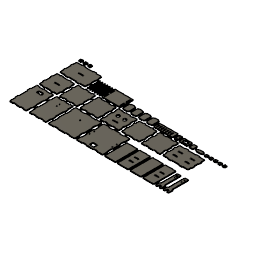
ROBERTO_PECAS_ESPALHADAS (Autodesk Fusion 360 design; units mm, degrees)
part number: 2026-10-26-13-50-44-096
part number: 2026-10-26-13-50-44-308
part number: 2026-10-26-13-50-44-466
part number: 2026-10-26-13-50-44-592
part number: 2026-10-26-13-50-44-704
part number: 2026-10-26-13-50-44-855
part number: 2026-10-26-13-50-44-911
part number: 2026-10-26-13-50-44-996
part number: 2026-10-26-13-50-45-058
part number: 2026-10-26-13-50-45-187
part number: 2026-10-26-13-50-45-294
part number: 2026-10-26-13-50-45-413
part number: 2026-10-26-13-50-45-575
part number: 2026-10-26-13-50-45-725
part number: 2026-10-26-13-50-45-862
part number: 2026-10-26-13-50-46-044
part number: 2026-10-26-13-50-46-201
part number: 2026-10-26-13-50-46-377
part number: 2026-10-26-13-50-46-593
part number: 2026-10-26-13-50-46-819
part number: 2026-10-26-13-50-46-915
part number: 2026-10-26-13-50-47-022
part number: 2026-10-26-13-50-47-157
part number: 2026-10-26-13-50-47-275
part number: 2026-10-26-13-50-47-377
part number: 2026-10-26-13-50-47-495
part number: 2026-10-26-13-50-47-649
part number: 2026-10-26-13-50-47-793
part number: 2026-10-26-13-50-47-947
part number: 2026-10-26-13-50-48-095
part number: 2026-10-26-13-50-48-228
part number: 2026-10-26-13-50-48-464
part number: 2026-10-26-13-50-48-602
part number: 2026-10-26-13-50-48-754
part number: 2026-10-26-13-50-48-889
part number: 2026-10-26-13-50-49-059
part number: 2026-10-26-13-50-49-210
part number: 2026-10-26-13-50-49-351
part number: 2026-10-26-13-50-49-502
part number: 2026-10-26-13-50-49-657
part number: 2026-10-26-13-50-49-817
part number: 2026-10-26-13-50-49-993
part number: 2026-10-26-13-50-50-198
Autodesk Fusion 360 part; units mm, degrees
sketch "Esboço1" plane through (0, 0, 0) normal (0, 0, 1) x (1, 0, 0) in component "C_DIR"
  line L0 (36.1, 0) -> (58.9, 0)
  line L1 (58.9, 0) -> (58.9, 3.1)
  line L2 (58.9, 3.1) -> (74.1, 3.1)
  line L3 (74.1, 3.1) -> (74.1, 0)
  line L4 (74.1, 0) -> (92, 0)
  line L5 (92, 0) -> (92, 29.25)
  line L6 (92, 29.25) -> (95, 29.25)
  line L7 (95, 29.25) -> (95, 51.05)
  line L8 (95, 51.05) -> (92, 51.05)
  line L9 (92, 51.05) -> (92, 94.95)
  line L10 (92, 94.95) -> (95, 94.95)
  line L11 (95, 94.95) -> (95, 116.75)
  line L12 (95, 116.75) -> (92, 116.75)
  line L13 (92, 116.75) -> (92, 146)
  line L14 (92, 146) -> (74.1, 146)
  line L15 (74.1, 146) -> (74.1, 142.9)
  line L16 (74.1, 142.9) -> (58.9, 142.9)
  line L17 (58.9, 142.9) -> (58.9, 146)
  line L18 (58.9, 146) -> (36.1, 146)
  line L19 (36.1, 146) -> (36.1, 142.9)
  line L20 (36.1, 142.9) -> (20.9, 142.9)
  line L21 (20.9, 142.9) -> (20.9, 146)
  line L22 (20.9, 146) -> (3, 146)
  line L23 (3, 146) -> (3, 116.75)
  line L24 (3, 116.75) -> (0, 116.75)
  line L25 (0, 116.75) -> (0, 94.95)
  line L26 (0, 94.95) -> (3, 94.95)
  line L27 (3, 94.95) -> (3, 51.05)
  line L28 (3, 51.05) -> (0, 51.05)
  line L29 (0, 51.05) -> (0, 29.25)
  line L30 (0, 29.25) -> (3, 29.25)
  line L31 (3, 29.25) -> (3, 0)
  line L32 (3, 0) -> (20.9, 0)
  line L33 (20.9, 0) -> (20.9, 3.1)
  line L34 (20.9, 3.1) -> (36.1, 3.1)
  line L35 (36.1, 3.1) -> (36.1, 0)
  line L36 (35.75, 111.6) -> (35.75, 124.4)
  line L37 (35.75, 124.4) -> (59.25, 124.4)
  line L38 (59.25, 124.4) -> (59.25, 111.6)
  line L39 (59.25, 111.6) -> (35.75, 111.6)
  circle A0 centre (33.5, 118) radius 1.1
  circle A1 centre (61.5, 118) radius 1.1
extrude "C_DIR" add sketch "Esboço1" along normal blind 3 makes body 1 in component "C_DIR"
sketch "Esboço1 (2)" plane through (0, 0, 0) normal (0, 0, 1) x (1, 0, 0) in component "C_ESQ"
  line L0 (92, 29.25) -> (95, 29.25)
  line L1 (95, 29.25) -> (95, 51.05)
  line L2 (95, 51.05) -> (92, 51.05)
  line L3 (92, 51.05) -> (92, 94.95)
  line L4 (92, 94.95) -> (95, 94.95)
  line L5 (95, 94.95) -> (95, 116.75)
  line L6 (95, 116.75) -> (92, 116.75)
  line L7 (92, 116.75) -> (92, 146)
  line L8 (92, 146) -> (74.1, 146)
  line L9 (74.1, 146) -> (74.1, 142.9)
  line L10 (74.1, 142.9) -> (58.9, 142.9)
  line L11 (58.9, 142.9) -> (58.9, 146)
  line L12 (58.9, 146) -> (36.1, 146)
  line L13 (36.1, 146) -> (36.1, 142.9)
  line L14 (36.1, 142.9) -> (20.9, 142.9)
  line L15 (20.9, 142.9) -> (20.9, 146)
  line L16 (20.9, 146) -> (3, 146)
  line L17 (3, 146) -> (3, 116.75)
  line L18 (3, 116.75) -> (0, 116.75)
  line L19 (0, 116.75) -> (0, 94.95)
  line L20 (0, 94.95) -> (3, 94.95)
  line L21 (3, 94.95) -> (3, 51.05)
  line L22 (3, 51.05) -> (0, 51.05)
  line L23 (0, 51.05) -> (0, 29.25)
  line L24 (0, 29.25) -> (3, 29.25)
  line L25 (3, 29.25) -> (3, 0)
  line L26 (3, 0) -> (20.9, 0)
  line L27 (20.9, 0) -> (20.9, 3.1)
  line L28 (20.9, 3.1) -> (36.1, 3.1)
  line L29 (36.1, 3.1) -> (36.1, 0)
  line L30 (36.1, 0) -> (58.9, 0)
  line L31 (58.9, 0) -> (58.9, 3.1)
  line L32 (58.9, 3.1) -> (74.1, 3.1)
  line L33 (74.1, 3.1) -> (74.1, 0)
  line L34 (74.1, 0) -> (92, 0)
  line L35 (92, 0) -> (92, 29.25)
  circle A0 centre (47.5, 118) radius 1.7
  circle A1 centre (47.5, 103) radius 1.7
extrude "C_ESQ" add sketch "Esboço1 (2)" along normal blind 3 separate body makes body 2 in component "C_ESQ"
sketch "Esboço1 (3)" plane through (0, 0, 0) normal (0, 0, 1) x (1, 0, 0) in component "C_FRENTE"
  line L0 (136.9, 94.9) -> (136.9, 116.8)
  line L1 (136.9, 116.8) -> (140, 116.8)
  line L2 (140, 116.8) -> (140, 146)
  line L3 (140, 146) -> (109.2, 146)
  line L4 (109.2, 146) -> (109.2, 142.9)
  line L5 (109.2, 142.9) -> (89.6, 142.9)
  line L6 (89.6, 142.9) -> (89.6, 146)
  line L7 (89.6, 146) -> (50.4, 146)
  line L8 (50.4, 146) -> (50.4, 142.9)
  line L9 (50.4, 142.9) -> (30.8, 142.9)
  line L10 (30.8, 142.9) -> (30.8, 146)
  line L11 (30.8, 146) -> (0, 146)
  line L12 (0, 146) -> (0, 116.8)
  line L13 (0, 116.8) -> (3.1, 116.8)
  line L14 (3.1, 116.8) -> (3.1, 94.9)
  line L15 (3.1, 94.9) -> (0, 94.9)
  line L16 (0, 94.9) -> (0, 51.1)
  line L17 (0, 51.1) -> (3.1, 51.1)
  line L18 (3.1, 51.1) -> (3.1, 29.2)
  line L19 (3.1, 29.2) -> (0, 29.2)
  line L20 (0, 29.2) -> (0, 0)
  line L21 (0, 0) -> (30.8, 0)
  line L22 (30.8, 0) -> (30.8, 3.1)
  line L23 (30.8, 3.1) -> (50.4, 3.1)
  line L24 (50.4, 3.1) -> (50.4, 0)
  line L25 (50.4, 0) -> (89.6, 0)
  line L26 (89.6, 0) -> (89.6, 3.1)
  line L27 (89.6, 3.1) -> (109.2, 3.1)
  line L28 (109.2, 3.1) -> (109.2, 0)
  line L29 (109.2, 0) -> (140, 0)
  line L30 (140, 0) -> (140, 29.2)
  line L31 (140, 29.2) -> (136.9, 29.2)
  line L32 (136.9, 29.2) -> (136.9, 51.1)
  line L33 (136.9, 51.1) -> (140, 51.1)
  line L34 (140, 51.1) -> (140, 94.9)
  line L35 (140, 94.9) -> (136.9, 94.9)
  circle A0 centre (70, 99.28) radius 2.6
extrude "C_FRENTE" add sketch "Esboço1 (3)" along normal blind 3 separate body makes body 3 in component "C_FRENTE"
sketch "Esboço1 (4)" plane through (0, 0, 0) normal (0, 0, 1) x (1, 0, 0) in component "C_TRAS"
  line L0 (89.6, 0) -> (89.6, 3.1)
  line L1 (89.6, 3.1) -> (109.2, 3.1)
  line L2 (109.2, 3.1) -> (109.2, 0)
  line L3 (109.2, 0) -> (140, 0)
  line L4 (140, 0) -> (140, 29.2)
  line L5 (140, 29.2) -> (136.9, 29.2)
  line L6 (136.9, 29.2) -> (136.9, 51.1)
  line L7 (136.9, 51.1) -> (140, 51.1)
  line L8 (140, 51.1) -> (140, 94.9)
  line L9 (140, 94.9) -> (136.9, 94.9)
  line L10 (136.9, 94.9) -> (136.9, 116.8)
  line L11 (136.9, 116.8) -> (140, 116.8)
  line L12 (140, 116.8) -> (140, 146)
  line L13 (140, 146) -> (109.2, 146)
  line L14 (109.2, 146) -> (109.2, 142.9)
  line L15 (109.2, 142.9) -> (89.6, 142.9)
  line L16 (89.6, 142.9) -> (89.6, 146)
  line L17 (89.6, 146) -> (50.4, 146)
  line L18 (50.4, 146) -> (50.4, 142.9)
  line L19 (50.4, 142.9) -> (30.8, 142.9)
  line L20 (30.8, 142.9) -> (30.8, 146)
  line L21 (30.8, 146) -> (0, 146)
  line L22 (0, 146) -> (0, 116.8)
  line L23 (0, 116.8) -> (3.1, 116.8)
  line L24 (3.1, 116.8) -> (3.1, 94.9)
  line L25 (3.1, 94.9) -> (0, 94.9)
  line L26 (0, 94.9) -> (0, 51.1)
  line L27 (0, 51.1) -> (3.1, 51.1)
  line L28 (3.1, 51.1) -> (3.1, 29.2)
  line L29 (3.1, 29.2) -> (0, 29.2)
  line L30 (0, 29.2) -> (0, 0)
  line L31 (0, 0) -> (30.8, 0)
  line L32 (30.8, 0) -> (30.8, 3.1)
  line L33 (30.8, 3.1) -> (50.4, 3.1)
  line L34 (50.4, 3.1) -> (50.4, 0)
  line L35 (50.4, 0) -> (89.6, 0)
  line L36 (58, 30) -> (82, 30)
  line L37 (82, 30) -> (82, 12)
  line L38 (82, 12) -> (58, 12)
  line L39 (58, 12) -> (58, 30)
  circle A0 centre (10, 61.32) radius 1.7
  circle A1 centre (10, 84.68) radius 1.7
  circle A2 centre (130, 61.32) radius 1.7
  circle A3 centre (130, 84.68) radius 1.7
extrude "C_TRAS" add sketch "Esboço1 (4)" along normal blind 3 separate body makes body 4 in component "C_TRAS"
sketch "Esboço1 (5)" plane through (0, 0, 0) normal (0, 0, 1) x (1, 0, 0) in component "P_D1"
  line L0 (0, 0) -> (58, 0)
  line L1 (58, 0) -> (58, 120)
  line L2 (58, 120) -> (0, 120)
  line L3 (0, 120) -> (0, 0)
extrude "P_D1" add sketch "Esboço1 (5)" along normal blind 3 separate body makes body 5 in component "P_D1"
sketch "Esboço1 (6)" plane through (0, 0, 0) normal (0, 0, 1) x (1, 0, 0) in component "P_D2"
  line L0 (18.95, 44.2) -> (18.95, 47.3)
  line L1 (18.95, 47.3) -> (39.05, 47.3)
  line L2 (39.05, 47.3) -> (39.05, 44.2)
  line L3 (39.05, 44.2) -> (18.95, 44.2)
  line L4 (0, 0) -> (58, 0)
  line L5 (58, 0) -> (58, 120)
  line L6 (58, 120) -> (0, 120)
  line L7 (0, 120) -> (0, 0)
  line L8 (39.05, 72.7) -> (18.95, 72.7)
  line L9 (18.95, 72.7) -> (18.95, 75.8)
  line L10 (18.95, 75.8) -> (39.05, 75.8)
  line L11 (39.05, 75.8) -> (39.05, 72.7)
extrude "P_D2" add sketch "Esboço1 (6)" along normal blind 3 separate body makes body 6 in component "P_D2"
sketch "Esboço1 (7)" plane through (0, 0, 0) normal (0, 0, 1) x (1, 0, 0) in component "P_E1"
  line L0 (0, 0) -> (58, 0)
  line L1 (58, 0) -> (58, 120)
  line L2 (58, 120) -> (0, 120)
  line L3 (0, 120) -> (0, 0)
extrude "P_E1" add sketch "Esboço1 (7)" along normal blind 3 separate body makes body 7 in component "P_E1"
sketch "Esboço1 (8)" plane through (0, 0, 0) normal (0, 0, 1) x (1, 0, 0) in component "P_E2"
  line L0 (18.95, 44.2) -> (18.95, 47.3)
  line L1 (18.95, 47.3) -> (39.05, 47.3)
  line L2 (39.05, 47.3) -> (39.05, 44.2)
  line L3 (39.05, 44.2) -> (18.95, 44.2)
  line L4 (0, 0) -> (58, 0)
  line L5 (58, 0) -> (58, 120)
  line L6 (58, 120) -> (0, 120)
  line L7 (0, 120) -> (0, 0)
  line L8 (39.05, 72.7) -> (18.95, 72.7)
  line L9 (18.95, 72.7) -> (18.95, 75.8)
  line L10 (18.95, 75.8) -> (39.05, 75.8)
  line L11 (39.05, 75.8) -> (39.05, 72.7)
extrude "P_E2" add sketch "Esboço1 (8)" along normal blind 3 separate body makes body 8 in component "P_E2"
sketch "Esboço1 (9)" plane through (0, 0, 0) normal (0, 0, 1) x (1, 0, 0) in component "A_D_MOVEL"
  line L0 (-10, 12) -> (10, 12)
  line L1 (10, 12) -> (10, -75)
  line L2 (10, -75) -> (15, -75)
  line L3 (15, -75) -> (15, -100)
  line L4 (15, -100) -> (5, -100)
  line L5 (5, -100) -> (5, -88)
  line L6 (5, -88) -> (-5, -88)
  line L7 (-5, -88) -> (-5, -100)
  line L8 (-5, -100) -> (-15, -100)
  line L9 (-15, -100) -> (-15, -75)
  line L10 (-15, -75) -> (-10, -75)
  line L11 (-10, -75) -> (-10, 12)
  circle A0 centre (0, 0) radius 3.5
  circle A1 centre (0, -7) radius 1
  circle A2 centre (0, -14) radius 1
extrude "A_D_MOVEL" add sketch "Esboço1 (9)" along normal blind 3 separate body makes body 9 in component "A_D_MOVEL"
sketch "Esboço1 (10)" plane through (0, 0, 0) normal (0, 0, 1) x (1, 0, 0) in component "A_E_FIXO"
  line L0 (-10, 12) -> (10, 12)
  line L1 (10, 12) -> (10, -75)
  line L2 (10, -75) -> (15, -75)
  line L3 (15, -75) -> (15, -100)
  line L4 (15, -100) -> (5, -100)
  line L5 (5, -100) -> (5, -88)
  line L6 (5, -88) -> (-5, -88)
  line L7 (-5, -88) -> (-5, -100)
  line L8 (-5, -100) -> (-15, -100)
  line L9 (-15, -100) -> (-15, -75)
  line L10 (-15, -75) -> (-10, -75)
  line L11 (-10, -75) -> (-10, 12)
  circle A0 centre (0, 0) radius 1.7
  circle A1 centre (0, -15) radius 1.7
extrude "A_E_FIXO" add sketch "Esboço1 (10)" along normal blind 3 separate body makes body 10 in component "A_E_FIXO"
sketch "Esboço1 (11)" plane through (0, 0, 0) normal (0, 0, 1) x (1, 0, 0) in component "H_BASE"
  line L0 (37.95, 48.45) -> (37.95, 51.55)
  line L1 (37.95, 51.55) -> (62.05, 51.55)
  line L2 (62.05, 51.55) -> (62.05, 48.45)
  line L3 (62.05, 48.45) -> (37.95, 48.45)
  line L4 (35.95, 3) -> (64.05, 3)
  line L5 (64.05, 3) -> (64.05, 0)
  line L6 (64.05, 0) -> (77.95, 0)
  line L7 (77.95, 0) -> (77.95, 3)
  line L8 (77.95, 3) -> (97, 3)
  line L9 (97, 3) -> (97, 22.05)
  line L10 (97, 22.05) -> (100, 22.05)
  line L11 (100, 22.05) -> (100, 37.95)
  line L12 (100, 37.95) -> (97, 37.95)
  line L13 (97, 37.95) -> (97, 62.05)
  line L14 (97, 62.05) -> (100, 62.05)
  line L15 (100, 62.05) -> (100, 77.95)
  line L16 (100, 77.95) -> (97, 77.95)
  line L17 (97, 77.95) -> (97, 97)
  line L18 (97, 97) -> (77.95, 97)
  line L19 (77.95, 97) -> (77.95, 100)
  line L20 (77.95, 100) -> (64.05, 100)
  line L21 (64.05, 100) -> (64.05, 97)
  line L22 (64.05, 97) -> (35.95, 97)
  line L23 (35.95, 97) -> (35.95, 100)
  line L24 (35.95, 100) -> (22.05, 100)
  line L25 (22.05, 100) -> (22.05, 97)
  line L26 (22.05, 97) -> (3, 97)
  line L27 (3, 97) -> (3, 77.95)
  line L28 (3, 77.95) -> (0, 77.95)
  line L29 (0, 77.95) -> (0, 62.05)
  line L30 (0, 62.05) -> (3, 62.05)
  line L31 (3, 62.05) -> (3, 37.95)
  line L32 (3, 37.95) -> (0, 37.95)
  line L33 (0, 37.95) -> (0, 22.05)
  line L34 (0, 22.05) -> (3, 22.05)
  line L35 (3, 22.05) -> (3, 3)
  line L36 (3, 3) -> (22.05, 3)
  line L37 (22.05, 3) -> (22.05, 0)
  line L38 (22.05, 0) -> (35.95, 0)
  line L39 (35.95, 0) -> (35.95, 3)
extrude "H_BASE" add sketch "Esboço1 (11)" along normal blind 3 separate body makes body 11 in component "H_BASE"
sketch "Esboço1 (12)" plane through (0, 0, 0) normal (0, 0, 1) x (1, 0, 0) in component "H_DIR"
  line L0 (97, 20.05) -> (100, 20.05)
  line L1 (100, 20.05) -> (100, 34.95)
  line L2 (100, 34.95) -> (97, 34.95)
  line L3 (97, 34.95) -> (97, 65.05)
  line L4 (97, 65.05) -> (100, 65.05)
  line L5 (100, 65.05) -> (100, 79.95)
  line L6 (100, 79.95) -> (97, 79.95)
  line L7 (97, 79.95) -> (97, 100)
  line L8 (97, 100) -> (78, 100)
  line L9 (78, 100) -> (78, 96.9)
  line L10 (78, 96.9) -> (62, 96.9)
  line L11 (62, 96.9) -> (62, 100)
  line L12 (62, 100) -> (38, 100)
  line L13 (38, 100) -> (38, 96.9)
  line L14 (38, 96.9) -> (22, 96.9)
  line L15 (22, 96.9) -> (22, 100)
  line L16 (22, 100) -> (3, 100)
  line L17 (3, 100) -> (3, 79.95)
  line L18 (3, 79.95) -> (0, 79.95)
  line L19 (0, 79.95) -> (0, 65.05)
  line L20 (0, 65.05) -> (3, 65.05)
  line L21 (3, 65.05) -> (3, 34.95)
  line L22 (3, 34.95) -> (0, 34.95)
  line L23 (0, 34.95) -> (0, 20.05)
  line L24 (0, 20.05) -> (3, 20.05)
  line L25 (3, 20.05) -> (3, 0)
  line L26 (3, 0) -> (22, 0)
  line L27 (22, 0) -> (22, 3.1)
  line L28 (22, 3.1) -> (38, 3.1)
  line L29 (38, 3.1) -> (38, 0)
  line L30 (38, 0) -> (62, 0)
  line L31 (62, 0) -> (62, 3.1)
  line L32 (62, 3.1) -> (78, 3.1)
  line L33 (78, 3.1) -> (78, 0)
  line L34 (78, 0) -> (97, 0)
  line L35 (97, 0) -> (97, 20.05)
extrude "H_DIR" add sketch "Esboço1 (12)" along normal blind 3 separate body makes body 12 in component "H_DIR"
sketch "Esboço1 (13)" plane through (0, 0, 0) normal (0, 0, 1) x (1, 0, 0) in component "H_ESQ"
  line L0 (97, 20.05) -> (100, 20.05)
  line L1 (100, 20.05) -> (100, 34.95)
  line L2 (100, 34.95) -> (97, 34.95)
  line L3 (97, 34.95) -> (97, 65.05)
  line L4 (97, 65.05) -> (100, 65.05)
  line L5 (100, 65.05) -> (100, 79.95)
  line L6 (100, 79.95) -> (97, 79.95)
  line L7 (97, 79.95) -> (97, 100)
  line L8 (97, 100) -> (78, 100)
  line L9 (78, 100) -> (78, 96.9)
  line L10 (78, 96.9) -> (62, 96.9)
  line L11 (62, 96.9) -> (62, 100)
  line L12 (62, 100) -> (38, 100)
  line L13 (38, 100) -> (38, 96.9)
  line L14 (38, 96.9) -> (22, 96.9)
  line L15 (22, 96.9) -> (22, 100)
  line L16 (22, 100) -> (3, 100)
  line L17 (3, 100) -> (3, 79.95)
  line L18 (3, 79.95) -> (0, 79.95)
  line L19 (0, 79.95) -> (0, 65.05)
  line L20 (0, 65.05) -> (3, 65.05)
  line L21 (3, 65.05) -> (3, 34.95)
  line L22 (3, 34.95) -> (0, 34.95)
  line L23 (0, 34.95) -> (0, 20.05)
  line L24 (0, 20.05) -> (3, 20.05)
  line L25 (3, 20.05) -> (3, 0)
  line L26 (3, 0) -> (22, 0)
  line L27 (22, 0) -> (22, 3.1)
  line L28 (22, 3.1) -> (38, 3.1)
  line L29 (38, 3.1) -> (38, 0)
  line L30 (38, 0) -> (62, 0)
  line L31 (62, 0) -> (62, 3.1)
  line L32 (62, 3.1) -> (78, 3.1)
  line L33 (78, 3.1) -> (78, 0)
  line L34 (78, 0) -> (97, 0)
  line L35 (97, 0) -> (97, 20.05)
extrude "H_ESQ" add sketch "Esboço1 (13)" along normal blind 3 separate body makes body 13 in component "H_ESQ"
sketch "Esboço1 (14)" plane through (0, 0, 0) normal (0, 0, 1) x (1, 0, 0) in component "H_FRENTE"
  line L0 (64, 0) -> (64, 3.1)
  line L1 (64, 3.1) -> (78, 3.1)
  line L2 (78, 3.1) -> (78, 0)
  line L3 (78, 0) -> (100, 0)
  line L4 (100, 0) -> (100, 20)
  line L5 (100, 20) -> (96.9, 20)
  line L6 (96.9, 20) -> (96.9, 35)
  line L7 (96.9, 35) -> (100, 35)
  line L8 (100, 35) -> (100, 65)
  line L9 (100, 65) -> (96.9, 65)
  line L10 (96.9, 65) -> (96.9, 80)
  line L11 (96.9, 80) -> (100, 80)
  line L12 (100, 80) -> (100, 100)
  line L13 (100, 100) -> (78, 100)
  line L14 (78, 100) -> (78, 96.9)
  line L15 (78, 96.9) -> (64, 96.9)
  line L16 (64, 96.9) -> (64, 100)
  line L17 (64, 100) -> (36, 100)
  line L18 (36, 100) -> (36, 96.9)
  line L19 (36, 96.9) -> (22, 96.9)
  line L20 (22, 96.9) -> (22, 100)
  line L21 (22, 100) -> (0, 100)
  line L22 (0, 100) -> (0, 80)
  line L23 (0, 80) -> (3.1, 80)
  line L24 (3.1, 80) -> (3.1, 65)
  line L25 (3.1, 65) -> (0, 65)
  line L26 (0, 65) -> (0, 35)
  line L27 (0, 35) -> (3.1, 35)
  line L28 (3.1, 35) -> (3.1, 20)
  line L29 (3.1, 20) -> (0, 20)
  line L30 (0, 20) -> (0, 0)
  line L31 (0, 0) -> (22, 0)
  line L32 (22, 0) -> (22, 3.1)
  line L33 (22, 3.1) -> (36, 3.1)
  line L34 (36, 3.1) -> (36, 0)
  line L35 (36, 0) -> (64, 0)
  line L36 (62, 30) -> (38, 30)
  line L37 (38, 30) -> (38, 33)
  line L38 (38, 33) -> (62, 33)
  line L39 (62, 33) -> (62, 30)
  circle A0 centre (32, 65) radius 8
  circle A1 centre (68, 65) radius 8
extrude "H_FRENTE" add sketch "Esboço1 (14)" along normal blind 3 separate body makes body 14 in component "H_FRENTE"
sketch "Esboço1 (15)" plane through (0, 0, 0) normal (0, 0, 1) x (1, 0, 0) in component "H_TOPO"
  line L0 (64.05, 0) -> (77.95, 0)
  line L1 (77.95, 0) -> (77.95, 3)
  line L2 (77.95, 3) -> (97, 3)
  line L3 (97, 3) -> (97, 22.05)
  line L4 (97, 22.05) -> (100, 22.05)
  line L5 (100, 22.05) -> (100, 37.95)
  line L6 (100, 37.95) -> (97, 37.95)
  line L7 (97, 37.95) -> (97, 62.05)
  line L8 (97, 62.05) -> (100, 62.05)
  line L9 (100, 62.05) -> (100, 77.95)
  line L10 (100, 77.95) -> (97, 77.95)
  line L11 (97, 77.95) -> (97, 97)
  line L12 (97, 97) -> (77.95, 97)
  line L13 (77.95, 97) -> (77.95, 100)
  line L14 (77.95, 100) -> (64.05, 100)
  line L15 (64.05, 100) -> (64.05, 97)
  line L16 (64.05, 97) -> (35.95, 97)
  line L17 (35.95, 97) -> (35.95, 100)
  line L18 (35.95, 100) -> (22.05, 100)
  line L19 (22.05, 100) -> (22.05, 97)
  line L20 (22.05, 97) -> (3, 97)
  line L21 (3, 97) -> (3, 77.95)
  line L22 (3, 77.95) -> (0, 77.95)
  line L23 (0, 77.95) -> (0, 62.05)
  line L24 (0, 62.05) -> (3, 62.05)
  line L25 (3, 62.05) -> (3, 37.95)
  line L26 (3, 37.95) -> (0, 37.95)
  line L27 (0, 37.95) -> (0, 22.05)
  line L28 (0, 22.05) -> (3, 22.05)
  line L29 (3, 22.05) -> (3, 3)
  line L30 (3, 3) -> (22.05, 3)
  line L31 (22.05, 3) -> (22.05, 0)
  line L32 (22.05, 0) -> (35.95, 0)
  line L33 (35.95, 0) -> (35.95, 3)
  line L34 (35.95, 3) -> (64.05, 3)
  line L35 (64.05, 3) -> (64.05, 0)
extrude "H_TOPO" add sketch "Esboço1 (15)" along normal blind 3 separate body makes body 15 in component "H_TOPO"
sketch "Esboço1 (16)" plane through (0, 0, 0) normal (0, 0, 1) x (1, 0, 0) in component "H_TRAS"
  line L0 (96.9, 65) -> (96.9, 80)
  line L1 (96.9, 80) -> (100, 80)
  line L2 (100, 80) -> (100, 100)
  line L3 (100, 100) -> (78, 100)
  line L4 (78, 100) -> (78, 96.9)
  line L5 (78, 96.9) -> (64, 96.9)
  line L6 (64, 96.9) -> (64, 100)
  line L7 (64, 100) -> (36, 100)
  line L8 (36, 100) -> (36, 96.9)
  line L9 (36, 96.9) -> (22, 96.9)
  line L10 (22, 96.9) -> (22, 100)
  line L11 (22, 100) -> (0, 100)
  line L12 (0, 100) -> (0, 80)
  line L13 (0, 80) -> (3.1, 80)
  line L14 (3.1, 80) -> (3.1, 65)
  line L15 (3.1, 65) -> (0, 65)
  line L16 (0, 65) -> (0, 35)
  line L17 (0, 35) -> (3.1, 35)
  line L18 (3.1, 35) -> (3.1, 20)
  line L19 (3.1, 20) -> (0, 20)
  line L20 (0, 20) -> (0, 0)
  line L21 (0, 0) -> (22, 0)
  line L22 (22, 0) -> (22, 3.1)
  line L23 (22, 3.1) -> (36, 3.1)
  line L24 (36, 3.1) -> (36, 0)
  line L25 (36, 0) -> (64, 0)
  line L26 (64, 0) -> (64, 3.1)
  line L27 (64, 3.1) -> (78, 3.1)
  line L28 (78, 3.1) -> (78, 0)
  line L29 (78, 0) -> (100, 0)
  line L30 (100, 0) -> (100, 20)
  line L31 (100, 20) -> (96.9, 20)
  line L32 (96.9, 20) -> (96.9, 35)
  line L33 (96.9, 35) -> (100, 35)
  line L34 (100, 35) -> (100, 65)
  line L35 (100, 65) -> (96.9, 65)
extrude "H_TRAS" add sketch "Esboço1 (16)" along normal blind 3 separate body makes body 16 in component "H_TRAS"
sketch "Esboço1 (17)" plane through (0, 0, 0) normal (0, 0, 1) x (1, 0, 0) in component "C_BASE"
  line L0 (50.35, 0) -> (50.35, 3)
  line L1 (50.35, 3) -> (89.65, 3)
  line L2 (89.65, 3) -> (89.65, 0)
  line L3 (89.65, 0) -> (109.15, 0)
  line L4 (109.15, 0) -> (109.15, 3)
  line L5 (109.15, 3) -> (137, 3)
  line L6 (137, 3) -> (137, 20.95)
  line L7 (137, 20.95) -> (140, 20.95)
  line L8 (140, 20.95) -> (140, 36.05)
  line L9 (140, 36.05) -> (137, 36.05)
  line L10 (137, 36.05) -> (137, 58.95)
  line L11 (137, 58.95) -> (140, 58.95)
  line L12 (140, 58.95) -> (140, 74.05)
  line L13 (140, 74.05) -> (137, 74.05)
  line L14 (137, 74.05) -> (137, 92)
  line L15 (137, 92) -> (109.15, 92)
  line L16 (109.15, 92) -> (109.15, 95)
  line L17 (109.15, 95) -> (89.65, 95)
  line L18 (89.65, 95) -> (89.65, 92)
  line L19 (89.65, 92) -> (50.35, 92)
  line L20 (50.35, 92) -> (50.35, 95)
  line L21 (50.35, 95) -> (30.85, 95)
  line L22 (30.85, 95) -> (30.85, 92)
  line L23 (30.85, 92) -> (3, 92)
  line L24 (3, 92) -> (3, 74.05)
  line L25 (3, 74.05) -> (0, 74.05)
  line L26 (0, 74.05) -> (0, 58.95)
  line L27 (0, 58.95) -> (3, 58.95)
  line L28 (3, 58.95) -> (3, 36.05)
  line L29 (3, 36.05) -> (0, 36.05)
  line L30 (0, 36.05) -> (0, 20.95)
  line L31 (0, 20.95) -> (3, 20.95)
  line L32 (3, 20.95) -> (3, 3)
  line L33 (3, 3) -> (30.85, 3)
  line L34 (30.85, 3) -> (30.85, 0)
  line L35 (30.85, 0) -> (50.35, 0)
  line L36 (27.75, 31.7) -> (27.75, 34.8)
  line L37 (27.75, 34.8) -> (47.85, 34.8)
  line L38 (47.85, 34.8) -> (47.85, 31.7)
  line L39 (47.85, 31.7) -> (27.75, 31.7)
  line L40 (47.85, 60.2) -> (27.75, 60.2)
  line L41 (27.75, 60.2) -> (27.75, 63.3)
  line L42 (27.75, 63.3) -> (47.85, 63.3)
  line L43 (47.85, 63.3) -> (47.85, 60.2)
  line L44 (112.25, 31.7) -> (92.15, 31.7)
  line L45 (92.15, 31.7) -> (92.15, 34.8)
  line L46 (92.15, 34.8) -> (112.25, 34.8)
  line L47 (112.25, 34.8) -> (112.25, 31.7)
  line L48 (112.25, 63.3) -> (112.25, 60.2)
  line L49 (112.25, 60.2) -> (92.15, 60.2)
  line L50 (92.15, 60.2) -> (92.15, 63.3)
  line L51 (92.15, 63.3) -> (112.25, 63.3)
extrude "C_BASE" add sketch "Esboço1 (17)" along normal blind 3 separate body makes body 17 in component "C_BASE"
sketch "Esboço1 (18)" plane through (0, 0, 0) normal (0, 0, 1) x (1, 0, 0) in component "C_TOPO"
  line L0 (57.95, 45.95) -> (57.95, 49.05)
  line L1 (57.95, 49.05) -> (82.05, 49.05)
  line L2 (82.05, 49.05) -> (82.05, 45.95)
  line L3 (82.05, 45.95) -> (57.95, 45.95)
  line L4 (50.35, 3) -> (89.65, 3)
  line L5 (89.65, 3) -> (89.65, 0)
  line L6 (89.65, 0) -> (109.15, 0)
  line L7 (109.15, 0) -> (109.15, 3)
  line L8 (109.15, 3) -> (137, 3)
  line L9 (137, 3) -> (137, 20.95)
  line L10 (137, 20.95) -> (140, 20.95)
  line L11 (140, 20.95) -> (140, 36.05)
  line L12 (140, 36.05) -> (137, 36.05)
  line L13 (137, 36.05) -> (137, 58.95)
  line L14 (137, 58.95) -> (140, 58.95)
  line L15 (140, 58.95) -> (140, 74.05)
  line L16 (140, 74.05) -> (137, 74.05)
  line L17 (137, 74.05) -> (137, 92)
  line L18 (137, 92) -> (109.15, 92)
  line L19 (109.15, 92) -> (109.15, 95)
  line L20 (109.15, 95) -> (89.65, 95)
  line L21 (89.65, 95) -> (89.65, 92)
  line L22 (89.65, 92) -> (50.35, 92)
  line L23 (50.35, 92) -> (50.35, 95)
  line L24 (50.35, 95) -> (30.85, 95)
  line L25 (30.85, 95) -> (30.85, 92)
  line L26 (30.85, 92) -> (3, 92)
  line L27 (3, 92) -> (3, 74.05)
  line L28 (3, 74.05) -> (0, 74.05)
  line L29 (0, 74.05) -> (0, 58.95)
  line L30 (0, 58.95) -> (3, 58.95)
  line L31 (3, 58.95) -> (3, 36.05)
  line L32 (3, 36.05) -> (0, 36.05)
  line L33 (0, 36.05) -> (0, 20.95)
  line L34 (0, 20.95) -> (3, 20.95)
  line L35 (3, 20.95) -> (3, 3)
  line L36 (3, 3) -> (30.85, 3)
  line L37 (30.85, 3) -> (30.85, 0)
  line L38 (30.85, 0) -> (50.35, 0)
  line L39 (50.35, 0) -> (50.35, 3)
extrude "C_TOPO" add sketch "Esboço1 (18)" along normal blind 3 separate body makes body 18 in component "C_TOPO"
sketch "Esboço1 (19)" plane through (0, 0, 0) normal (0, 0, 1) x (1, 0, 0) in component "I_APOIO00"
  line L0 (0, 0) -> (3, 0)
  line L1 (3, 0) -> (3, 70)
  line L2 (3, 70) -> (0, 70)
  line L3 (0, 70) -> (0, 0)
extrude "I_APOIO00" add sketch "Esboço1 (19)" along normal blind 3 separate body makes body 19 in component "I_APOIO00"
sketch "Esboço1 (20)" plane through (0, 0, 0) normal (0, 0, 1) x (1, 0, 0) in component "I_APOIO01"
  line L0 (0, 0) -> (3, 0)
  line L1 (3, 0) -> (3, 70)
  line L2 (3, 70) -> (0, 70)
  line L3 (0, 70) -> (0, 0)
extrude "I_APOIO01" add sketch "Esboço1 (20)" along normal blind 3 separate body makes body 20 in component "I_APOIO01"
sketch "Esboço1 (21)" plane through (0, 0, 0) normal (0, 0, 1) x (1, 0, 0) in component "I_APOIO02"
  line L0 (0, 0) -> (3, 0)
  line L1 (3, 0) -> (3, 70)
  line L2 (3, 70) -> (0, 70)
  line L3 (0, 70) -> (0, 0)
extrude "I_APOIO02" add sketch "Esboço1 (21)" along normal blind 3 separate body makes body 21 in component "I_APOIO02"
sketch "Esboço1 (22)" plane through (0, 0, 0) normal (0, 0, 1) x (1, 0, 0) in component "I_APOIO10"
  line L0 (0, 0) -> (3, 0)
  line L1 (3, 0) -> (3, 70)
  line L2 (3, 70) -> (0, 70)
  line L3 (0, 70) -> (0, 0)
extrude "I_APOIO10" add sketch "Esboço1 (22)" along normal blind 3 separate body makes body 22 in component "I_APOIO10"
sketch "Esboço1 (23)" plane through (0, 0, 0) normal (0, 0, 1) x (1, 0, 0) in component "I_APOIO11"
  line L0 (0, 0) -> (3, 0)
  line L1 (3, 0) -> (3, 70)
  line L2 (3, 70) -> (0, 70)
  line L3 (0, 70) -> (0, 0)
extrude "I_APOIO11" add sketch "Esboço1 (23)" along normal blind 3 separate body makes body 23 in component "I_APOIO11"
sketch "Esboço1 (24)" plane through (0, 0, 0) normal (0, 0, 1) x (1, 0, 0) in component "I_APOIO12"
  line L0 (0, 0) -> (3, 0)
  line L1 (3, 0) -> (3, 70)
  line L2 (3, 70) -> (0, 70)
  line L3 (0, 70) -> (0, 0)
extrude "I_APOIO12" add sketch "Esboço1 (24)" along normal blind 3 separate body makes body 24 in component "I_APOIO12"
sketch "Esboço1 (25)" plane through (0, 0, 0) normal (0, 0, 1) x (1, 0, 0) in component "I_BANDEJA"
  line L0 (50, 0) -> (50, 70)
  line L1 (50, 70) -> (-50, 70)
  line L2 (-50, 70) -> (-50, 0)
  line L3 (-50, 0) -> (50, 0)
  line L4 (41, 62) -> (44, 62)
  line L5 (44, 62) -> (44, 40)
  line L6 (44, 40) -> (41, 40)
  line L7 (41, 40) -> (41, 62)
  line L8 (-41, 8) -> (-44, 8)
  line L9 (-44, 8) -> (-44, 30)
  line L10 (-44, 30) -> (-41, 30)
  line L11 (-41, 30) -> (-41, 8)
  line L12 (44, 8) -> (41, 8)
  line L13 (41, 8) -> (41, 30)
  line L14 (41, 30) -> (44, 30)
  line L15 (44, 30) -> (44, 8)
  line L16 (-41, 40) -> (-44, 40)
  line L17 (-44, 40) -> (-44, 62)
  line L18 (-44, 62) -> (-41, 62)
  line L19 (-41, 62) -> (-41, 40)
extrude "I_BANDEJA" add sketch "Esboço1 (25)" along normal blind 3 separate body makes body 25 in component "I_BANDEJA"
sketch "Esboço1 (26)" plane through (0, 0, 0) normal (0, 0, 1) x (1, 0, 0) in component "L_D1"
  line L0 (-16, 0) -> (-9.95, 0)
  line L1 (-9.95, 0) -> (-9.95, -3)
  line L2 (-9.95, -3) -> (9.95, -3)
  line L3 (9.95, -3) -> (9.95, 0)
  line L4 (9.95, 0) -> (16, 0)
  line L5 (16, 0) -> (16, 38)
  line L6 (16, 38) -> (9.95, 38)
  line L7 (9.95, 38) -> (9.95, 41)
  line L8 (9.95, 41) -> (-9.95, 41)
  line L9 (-9.95, 41) -> (-9.95, 38)
  line L10 (-9.95, 38) -> (-16, 38)
  line L11 (-16, 38) -> (-16, 0)
extrude "L_D1" add sketch "Esboço1 (26)" along normal blind 3 separate body makes body 26 in component "L_D1"
sketch "Esboço1 (27)" plane through (0, 0, 0) normal (0, 0, 1) x (1, 0, 0) in component "L_D2"
  line L0 (-16, 0) -> (-9.95, 0)
  line L1 (-9.95, 0) -> (-9.95, -3)
  line L2 (-9.95, -3) -> (9.95, -3)
  line L3 (9.95, -3) -> (9.95, 0)
  line L4 (9.95, 0) -> (16, 0)
  line L5 (16, 0) -> (16, 38)
  line L6 (16, 38) -> (9.95, 38)
  line L7 (9.95, 38) -> (9.95, 41)
  line L8 (9.95, 41) -> (-9.95, 41)
  line L9 (-9.95, 41) -> (-9.95, 38)
  line L10 (-9.95, 38) -> (-16, 38)
  line L11 (-16, 38) -> (-16, 0)
extrude "L_D2" add sketch "Esboço1 (27)" along normal blind 3 separate body makes body 27 in component "L_D2"
sketch "Esboço1 (28)" plane through (0, 0, 0) normal (0, 0, 1) x (1, 0, 0) in component "L_E1"
  line L0 (-16, 0) -> (-9.95, 0)
  line L1 (-9.95, 0) -> (-9.95, -3)
  line L2 (-9.95, -3) -> (9.95, -3)
  line L3 (9.95, -3) -> (9.95, 0)
  line L4 (9.95, 0) -> (16, 0)
  line L5 (16, 0) -> (16, 38)
  line L6 (16, 38) -> (9.95, 38)
  line L7 (9.95, 38) -> (9.95, 41)
  line L8 (9.95, 41) -> (-9.95, 41)
  line L9 (-9.95, 41) -> (-9.95, 38)
  line L10 (-9.95, 38) -> (-16, 38)
  line L11 (-16, 38) -> (-16, 0)
extrude "L_E1" add sketch "Esboço1 (28)" along normal blind 3 separate body makes body 28 in component "L_E1"
sketch "Esboço1 (29)" plane through (0, 0, 0) normal (0, 0, 1) x (1, 0, 0) in component "L_E2"
  line L0 (-16, 0) -> (-9.95, 0)
  line L1 (-9.95, 0) -> (-9.95, -3)
  line L2 (-9.95, -3) -> (9.95, -3)
  line L3 (9.95, -3) -> (9.95, 0)
  line L4 (9.95, 0) -> (16, 0)
  line L5 (16, 0) -> (16, 38)
  line L6 (16, 38) -> (9.95, 38)
  line L7 (9.95, 38) -> (9.95, 41)
  line L8 (9.95, 41) -> (-9.95, 41)
  line L9 (-9.95, 41) -> (-9.95, 38)
  line L10 (-9.95, 38) -> (-16, 38)
  line L11 (-16, 38) -> (-16, 0)
extrude "L_E2" add sketch "Esboço1 (29)" along normal blind 3 separate body makes body 29 in component "L_E2"
sketch "Esboço1 (30)" plane through (0, 0, 0) normal (0, 0, 1) x (1, 0, 0) in component "TESTE_FEMEA"
  line L0 (100, 0) -> (100, 32)
  line L1 (100, 32) -> (0, 32)
  line L2 (0, 32) -> (0, 0)
  line L3 (0, 0) -> (100, 0)
  line L4 (80, 8) -> (80, 23)
  line L5 (80, 23) -> (83.2, 23)
  line L6 (83.2, 23) -> (83.2, 8)
  line L7 (83.2, 8) -> (80, 8)
  line L8 (71.15, 23) -> (71.15, 8)
  line L9 (71.15, 8) -> (68, 8)
  line L10 (68, 8) -> (68, 23)
  line L11 (68, 23) -> (71.15, 23)
  line L12 (56, 23) -> (59.1, 23)
  line L13 (59.1, 23) -> (59.1, 8)
  line L14 (59.1, 8) -> (56, 8)
  line L15 (56, 8) -> (56, 23)
  line L16 (10.9, 8) -> (8, 8)
  line L17 (8, 8) -> (8, 23)
  line L18 (8, 23) -> (10.9, 23)
  line L19 (10.9, 23) -> (10.9, 8)
  line L20 (22.95, 8) -> (20, 8)
  line L21 (20, 8) -> (20, 23)
  line L22 (20, 23) -> (22.95, 23)
  line L23 (22.95, 23) -> (22.95, 8)
  line L24 (35, 8) -> (32, 8)
  line L25 (32, 8) -> (32, 23)
  line L26 (32, 23) -> (35, 23)
  line L27 (35, 23) -> (35, 8)
  line L28 (44, 8) -> (44, 23)
  line L29 (44, 23) -> (47.05, 23)
  line L30 (47.05, 23) -> (47.05, 8)
  line L31 (47.05, 8) -> (44, 8)
extrude "TESTE_FEMEA" add sketch "Esboço1 (30)" along normal blind 3 separate body makes body 30 in component "TESTE_FEMEA"
sketch "Esboço1 (31)" plane through (0, 0, 0) normal (0, 0, 1) x (1, 0, 0) in component "A_E_ESP"
  line L0 (-8, -22) -> (8, -22)
  line L1 (8, -22) -> (8, 8)
  line L2 (8, 8) -> (-8, 8)
  line L3 (-8, 8) -> (-8, -22)
  circle A0 centre (0, 0) radius 1.7
  circle A1 centre (0, -15) radius 1.7
extrude "A_E_ESP" add sketch "Esboço1 (31)" along normal blind 3 separate body makes body 31 in component "A_E_ESP"
sketch "Esboço1 (32)" plane through (0, 0, 0) normal (0, 0, 1) x (1, 0, 0) in component "S_REFORCO"
  line L0 (-11.75, -6.4) -> (-11.75, 6.4)
  line L1 (-11.75, 6.4) -> (11.75, 6.4)
  line L2 (11.75, 6.4) -> (11.75, -6.4)
  line L3 (11.75, -6.4) -> (-11.75, -6.4)
  line L4 (-22, -14) -> (22, -14)
  line L5 (22, -14) -> (22, 14)
  line L6 (22, 14) -> (-22, 14)
  line L7 (-22, 14) -> (-22, -14)
  circle A0 centre (-14, 0) radius 1.1
  circle A1 centre (14, 0) radius 1.1
extrude "S_REFORCO" add sketch "Esboço1 (32)" along normal blind 3 separate body makes body 32 in component "S_REFORCO"
sketch "Esboço1 (33)" plane through (0, 0, 0) normal (0, 0, 1) x (1, 0, 0) in component "TESTE_MACHO"
  line L0 (0, 0) -> (20, 0)
  line L1 (20, 0) -> (20, 25)
  line L2 (20, 25) -> (0, 25)
  line L3 (0, 25) -> (0, 0)
extrude "TESTE_MACHO" add sketch "Esboço1 (33)" along normal blind 3 separate body makes body 33 in component "TESTE_MACHO"
sketch "Esboço1 (34)" plane through (0, 0, 0) normal (0, 0, 1) x (1, 0, 0) in component "N_PESCOCO"
  line L0 (-20, 0) -> (-11.95, 0)
  line L1 (-11.95, 0) -> (-11.95, -3)
  line L2 (-11.95, -3) -> (11.95, -3)
  line L3 (11.95, -3) -> (11.95, 0)
  line L4 (11.95, 0) -> (20, 0)
  line L5 (20, 0) -> (20, 10)
  line L6 (20, 10) -> (11.95, 10)
  line L7 (11.95, 10) -> (11.95, 13)
  line L8 (11.95, 13) -> (-11.95, 13)
  line L9 (-11.95, 13) -> (-11.95, 10)
  line L10 (-11.95, 10) -> (-20, 10)
  line L11 (-20, 10) -> (-20, 0)
extrude "N_PESCOCO" add sketch "Esboço1 (34)" along normal blind 3 separate body makes body 34 in component "N_PESCOCO"
sketch "Esboço1 (35)" plane through (0, 0, 0) normal (0, 0, 1) x (1, 0, 0) in component "T_CAPA_00"
  line L0 (0, 0) -> (14, 0)
  line L1 (14, 0) -> (14, 14)
  line L2 (14, 14) -> (0, 14)
  line L3 (0, 14) -> (0, 0)
  circle A0 centre (7, 7) radius 1.7
extrude "T_CAPA_00" add sketch "Esboço1 (35)" along normal blind 3 separate body makes body 35 in component "T_CAPA_00"
sketch "Esboço1 (36)" plane through (0, 0, 0) normal (0, 0, 1) x (1, 0, 0) in component "T_CAPA_01"
  line L0 (0, 0) -> (14, 0)
  line L1 (14, 0) -> (14, 14)
  line L2 (14, 14) -> (0, 14)
  line L3 (0, 14) -> (0, 0)
  circle A0 centre (7, 7) radius 1.7
extrude "T_CAPA_01" add sketch "Esboço1 (36)" along normal blind 3 separate body makes body 36 in component "T_CAPA_01"
sketch "Esboço1 (37)" plane through (0, 0, 0) normal (0, 0, 1) x (1, 0, 0) in component "T_CAPA_10"
  line L0 (0, 0) -> (14, 0)
  line L1 (14, 0) -> (14, 14)
  line L2 (14, 14) -> (0, 14)
  line L3 (0, 14) -> (0, 0)
  circle A0 centre (7, 7) radius 1.7
extrude "T_CAPA_10" add sketch "Esboço1 (37)" along normal blind 3 separate body makes body 37 in component "T_CAPA_10"
sketch "Esboço1 (38)" plane through (0, 0, 0) normal (0, 0, 1) x (1, 0, 0) in component "T_CAPA_11"
  line L0 (0, 0) -> (14, 0)
  line L1 (14, 0) -> (14, 14)
  line L2 (14, 14) -> (0, 14)
  line L3 (0, 14) -> (0, 0)
  circle A0 centre (7, 7) radius 1.7
extrude "T_CAPA_11" add sketch "Esboço1 (38)" along normal blind 3 separate body makes body 38 in component "T_CAPA_11"
sketch "Esboço1 (39)" plane through (0, 0, 0) normal (0, 0, 1) x (1, 0, 0) in component "T_PORCA_00"
  line L0 (0, 0) -> (14, 0)
  line L1 (14, 0) -> (14, 14)
  line L2 (14, 14) -> (0, 14)
  line L3 (0, 14) -> (0, 0)
  line L4 (10.2909, 7) -> (8.6454, 9.85)
  line L5 (8.6454, 9.85) -> (5.3546, 9.85)
  line L6 (5.3546, 9.85) -> (3.7091, 7)
  line L7 (3.7091, 7) -> (5.3546, 4.15)
  line L8 (5.3546, 4.15) -> (8.6454, 4.15)
  line L9 (8.6454, 4.15) -> (10.2909, 7)
extrude "T_PORCA_00" add sketch "Esboço1 (39)" along normal blind 3 separate body makes body 39 in component "T_PORCA_00"
sketch "Esboço1 (40)" plane through (0, 0, 0) normal (0, 0, 1) x (1, 0, 0) in component "T_PORCA_01"
  line L0 (0, 0) -> (14, 0)
  line L1 (14, 0) -> (14, 14)
  line L2 (14, 14) -> (0, 14)
  line L3 (0, 14) -> (0, 0)
  line L4 (10.2909, 7) -> (8.6454, 9.85)
  line L5 (8.6454, 9.85) -> (5.3546, 9.85)
  line L6 (5.3546, 9.85) -> (3.7091, 7)
  line L7 (3.7091, 7) -> (5.3546, 4.15)
  line L8 (5.3546, 4.15) -> (8.6454, 4.15)
  line L9 (8.6454, 4.15) -> (10.2909, 7)
extrude "T_PORCA_01" add sketch "Esboço1 (40)" along normal blind 3 separate body makes body 40 in component "T_PORCA_01"
sketch "Esboço1 (41)" plane through (0, 0, 0) normal (0, 0, 1) x (1, 0, 0) in component "T_PORCA_10"
  line L0 (0, 0) -> (14, 0)
  line L1 (14, 0) -> (14, 14)
  line L2 (14, 14) -> (0, 14)
  line L3 (0, 14) -> (0, 0)
  line L4 (10.2909, 7) -> (8.6454, 9.85)
  line L5 (8.6454, 9.85) -> (5.3546, 9.85)
  line L6 (5.3546, 9.85) -> (3.7091, 7)
  line L7 (3.7091, 7) -> (5.3546, 4.15)
  line L8 (5.3546, 4.15) -> (8.6454, 4.15)
  line L9 (8.6454, 4.15) -> (10.2909, 7)
extrude "T_PORCA_10" add sketch "Esboço1 (41)" along normal blind 3 separate body makes body 41 in component "T_PORCA_10"
sketch "Esboço1 (42)" plane through (0, 0, 0) normal (0, 0, 1) x (1, 0, 0) in component "T_PORCA_11"
  line L0 (0, 0) -> (14, 0)
  line L1 (14, 0) -> (14, 14)
  line L2 (14, 14) -> (0, 14)
  line L3 (0, 14) -> (0, 0)
  line L4 (10.2909, 7) -> (8.6454, 9.85)
  line L5 (8.6454, 9.85) -> (5.3546, 9.85)
  line L6 (5.3546, 9.85) -> (3.7091, 7)
  line L7 (3.7091, 7) -> (5.3546, 4.15)
  line L8 (5.3546, 4.15) -> (8.6454, 4.15)
  line L9 (8.6454, 4.15) -> (10.2909, 7)
extrude "T_PORCA_11" add sketch "Esboço1 (42)" along normal blind 3 separate body makes body 42 in component "T_PORCA_11"
component "C_DIR" placed x (1, 0, 0) y (0, 1, 0) z (0, 0, 1) at (0, 0, 0)
component "C_ESQ" placed x (1, 0, 0) y (0, 1, 0) z (0, 0, 1) at (105, 0, 0)
component "C_FRENTE" placed x (1, 0, 0) y (0, 1, 0) z (0, 0, 1) at (210, 0, 0)
component "C_TRAS" placed x (1, 0, 0) y (0, 1, 0) z (0, 0, 1) at (360, 0, 0)
component "P_D1" placed x (1, 0, 0) y (0, 1, 0) z (0, 0, 1) at (510, 0, 0)
component "P_D2" placed x (1, 0, 0) y (0, 1, 0) z (0, 0, 1) at (578, 0, 0)
component "P_E1" placed x (1, 0, 0) y (0, 1, 0) z (0, 0, 1) at (646, 0, 0)
component "P_E2" placed x (1, 0, 0) y (0, 1, 0) z (0, 0, 1) at (714, 0, 0)
component "A_D_MOVEL" placed x (1, 0, 0) y (0, 1, 0) z (0, 0, 1) at (797, 100, 0)
component "A_E_FIXO" placed x (1, 0, 0) y (0, 1, 0) z (0, 0, 1) at (837, 100, 0)
component "H_BASE" placed x (1, 0, 0) y (0, 1, 0) z (0, 0, 1) at (0, 156, 0)
component "H_DIR" placed x (1, 0, 0) y (0, 1, 0) z (0, 0, 1) at (110, 156, 0)
component "H_ESQ" placed x (1, 0, 0) y (0, 1, 0) z (0, 0, 1) at (220, 156, 0)
component "H_FRENTE" placed x (1, 0, 0) y (0, 1, 0) z (0, 0, 1) at (330, 156, 0)
component "H_TOPO" placed x (1, 0, 0) y (0, 1, 0) z (0, 0, 1) at (440, 156, 0)
component "H_TRAS" placed x (1, 0, 0) y (0, 1, 0) z (0, 0, 1) at (550, 156, 0)
component "C_BASE" placed x (1, 0, 0) y (0, 1, 0) z (0, 0, 1) at (660, 156, 0)
component "C_TOPO" placed x (1, 0, 0) y (0, 1, 0) z (0, 0, 1) at (0, 266, 0)
component "I_APOIO00" placed x (1, 0, 0) y (0, 1, 0) z (0, 0, 1) at (150, 266, 0)
component "I_APOIO01" placed x (1, 0, 0) y (0, 1, 0) z (0, 0, 1) at (163, 266, 0)
component "I_APOIO02" placed x (1, 0, 0) y (0, 1, 0) z (0, 0, 1) at (176, 266, 0)
component "I_APOIO10" placed x (1, 0, 0) y (0, 1, 0) z (0, 0, 1) at (189, 266, 0)
component "I_APOIO11" placed x (1, 0, 0) y (0, 1, 0) z (0, 0, 1) at (202, 266, 0)
component "I_APOIO12" placed x (1, 0, 0) y (0, 1, 0) z (0, 0, 1) at (215, 266, 0)
component "I_BANDEJA" placed x (1, 0, 0) y (0, 1, 0) z (0, 0, 1) at (278, 266, 0)
component "L_D1" placed x (1, 0, 0) y (0, 1, 0) z (0, 0, 1) at (354, 269, 0)
component "L_D2" placed x (1, 0, 0) y (0, 1, 0) z (0, 0, 1) at (396, 269, 0)
component "L_E1" placed x (1, 0, 0) y (0, 1, 0) z (0, 0, 1) at (438, 269, 0)
component "L_E2" placed x (1, 0, 0) y (0, 1, 0) z (0, 0, 1) at (480, 269, 0)
component "TESTE_FEMEA" placed x (1, 0, 0) y (0, 1, 0) z (0, 0, 1) at (506, 266, 0)
component "A_E_ESP" placed x (1, 0, 0) y (0, 1, 0) z (0, 0, 1) at (624, 288, 0)
component "S_REFORCO" placed x (1, 0, 0) y (0, 1, 0) z (0, 0, 1) at (664, 280, 0)
component "TESTE_MACHO" placed x (1, 0, 0) y (0, 1, 0) z (0, 0, 1) at (696, 266, 0)
component "N_PESCOCO" placed x (1, 0, 0) y (0, 1, 0) z (0, 0, 1) at (746, 269, 0)
component "T_CAPA_00" placed x (1, 0, 0) y (0, 1, 0) z (0, 0, 1) at (776, 266, 0)
component "T_CAPA_01" placed x (1, 0, 0) y (0, 1, 0) z (0, 0, 1) at (800, 266, 0)
component "T_CAPA_10" placed x (1, 0, 0) y (0, 1, 0) z (0, 0, 1) at (824, 266, 0)
component "T_CAPA_11" placed x (1, 0, 0) y (0, 1, 0) z (0, 0, 1) at (848, 266, 0)
component "T_PORCA_00" placed x (1, 0, 0) y (0, 1, 0) z (0, 0, 1) at (872, 266, 0)
component "T_PORCA_01" placed x (1, 0, 0) y (0, 1, 0) z (0, 0, 1) at (0, 371, 0)
component "T_PORCA_10" placed x (1, 0, 0) y (0, 1, 0) z (0, 0, 1) at (24, 371, 0)
component "T_PORCA_11" placed x (1, 0, 0) y (0, 1, 0) z (0, 0, 1) at (48, 371, 0)
